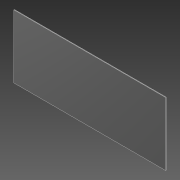
# Autodesk Inventor part: ant
Saved by Autodesk Inventor 2020.1 (Build 241239000, 239)
## iProperties
Created: 2026-10-11
Part Number: ant
Material: Generic
Document SubType Name: Modeling
Designer: willn
Density: 1 g/cm^3
Appearance: Smooth - Black
Author: willn
Autodesk Inventor part; units mm, degrees
ref_plane "YZ Plane" through (0, 0, 0) normal (1, 0, 0) x (0, 1, 0)
ref_plane "XZ Plane" through (0, 0, 0) normal (0, 1, 0) x (-1, 0, 0)
ref_plane "XY Plane" through (0, 0, 0) normal (0, 0, 1) x (1, 0, 0)
sketch "Sketch1" plane through (0, 0, 0) normal (0, 0, 1) x (1, 0, 0)
  line L0 (0, 0) -> (48, 0)
  line L1 (48, 0) -> (48, 20)
  line L2 (48, 20) -> (0, 20)
  line L3 (0, 20) -> (0, 0)
  dimension "d0" = 48
  dimension "d1" = 20
  constraints: 8 end point, 2 parallel, 1 horizontal, 1 perpendicular
  measures "d0" distance of L2.end L1.end
  measures "d1" distance of L1.end L0.end
extrude "Extrusion1" add sketch "Sketch1" along normal blind 0.2
body "Solid1"
